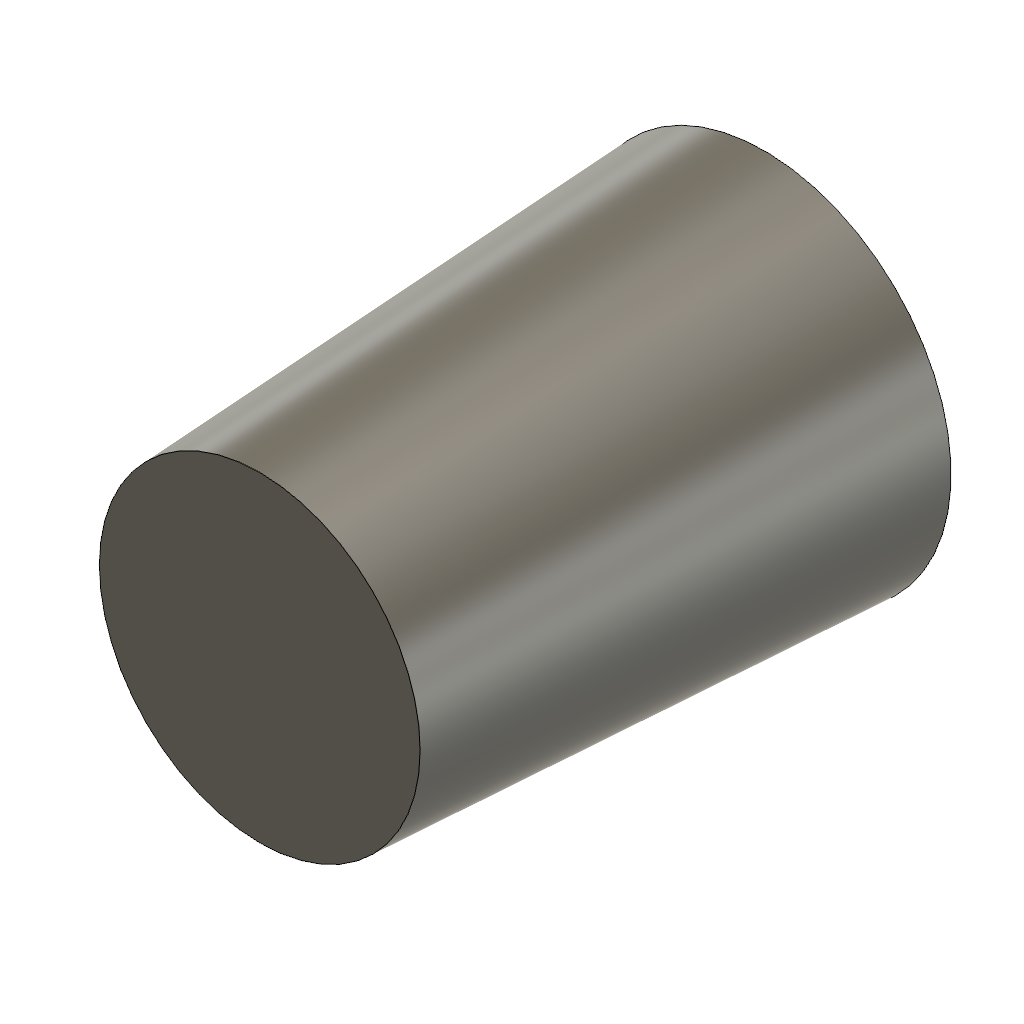
vendor_SourceFrame7deg27mmMinus3deg (Autodesk Fusion 360 design; units mm, degrees)
part number: 2026-10-20-18-12-40-233
Autodesk Fusion 360 part; units mm, degrees
sketch "ProbeProfile" plane through (0, 0, 0) normal (0, 0, 1) x (1, 0, 0)
  circle A0 centre (0, 0) radius 10
extrude "ProbeExtrusion" add sketch "ProbeProfile" along normal blind 27 draft -3
